Autodesk Fusion 360 part; units mm, degrees
(part 28 of 28)
  line L4452 (8.28, 5.03, -1.4859) -> (8.2704, 5.0319, -1.4859)
  line L4453 (8.2704, 5.0319, -1.4859) -> (8.2569, 5.0454, -1.4859)
  line L4454 (8.2569, 5.0454, -1.4859) -> (8.255, 5.055, -1.4859)
  line L4455 (8.255, 5.055, -1.4859) -> (8.255, 36.805, -1.4859)
  line L4456 (8.255, 36.805, -1.4859) -> (8.2569, 36.8146, -1.4859)
  line L4457 (8.2569, 36.8146, -1.4859) -> (8.2704, 36.8281, -1.4859)
  line L4458 (8.2704, 36.8281, -1.4859) -> (8.28, 36.83, -1.4859)
  line L4459 (8.28, 36.83, -1.4859) -> (66.065, 36.83, -1.4859)
  line L4460 (8.305, 36.78, -1.4859) -> (8.305, 5.08, -1.4859)
  line L4461 (8.305, 5.08, -1.4859) -> (66.04, 5.08, -1.4859)
  line L4462 (66.04, 5.08, -1.4859) -> (66.04, 36.78, -1.4859)
  line L4463 (66.04, 36.78, -1.4859) -> (62.89, 36.78, -1.4859)
  line L4464 (62.89, 36.78, -1.4859) -> (8.305, 36.78, -1.4859)
  line L4465 (127.025, 36.83, -1.4859) -> (127.0346, 36.8281, -1.4859)
  line L4466 (127.0346, 36.8281, -1.4859) -> (127.0481, 36.8146, -1.4859)
  line L4467 (127.0481, 36.8146, -1.4859) -> (127.05, 36.805, -1.4859)
  line L4468 (127.05, 36.805, -1.4859) -> (127.05, 5.055, -1.4859)
  line L4469 (127.05, 5.055, -1.4859) -> (127.0481, 5.0454, -1.4859)
  line L4470 (127.0481, 5.0454, -1.4859) -> (127.0346, 5.0319, -1.4859)
  line L4471 (127.0346, 5.0319, -1.4859) -> (127.025, 5.03, -1.4859)
  line L4472 (127.025, 5.03, -1.4859) -> (69.24, 5.03, -1.4859)
  line L4473 (69.24, 5.03, -1.4859) -> (69.2304, 5.0319, -1.4859)
  line L4474 (69.2304, 5.0319, -1.4859) -> (69.2169, 5.0454, -1.4859)
  line L4475 (69.2169, 5.0454, -1.4859) -> (69.215, 5.055, -1.4859)
  line L4476 (69.215, 5.055, -1.4859) -> (69.215, 36.805, -1.4859)
  line L4477 (69.215, 36.805, -1.4859) -> (69.2169, 36.8146, -1.4859)
  line L4478 (69.2169, 36.8146, -1.4859) -> (69.2304, 36.8281, -1.4859)
  line L4479 (69.2304, 36.8281, -1.4859) -> (69.24, 36.83, -1.4859)
  line L4480 (69.24, 36.83, -1.4859) -> (127.025, 36.83, -1.4859)
  line L4481 (69.265, 36.78, -1.4859) -> (69.265, 5.08, -1.4859)
  line L4482 (69.265, 5.08, -1.4859) -> (127, 5.08, -1.4859)
  line L4483 (127, 5.08, -1.4859) -> (127, 36.78, -1.4859)
  line L4484 (127, 36.78, -1.4859) -> (123.85, 36.78, -1.4859)
  line L4485 (123.85, 36.78, -1.4859) -> (69.265, 36.78, -1.4859)
  line L4486 (40.03, 97.79, -1.4859) -> (43.205, 97.79, -1.4859)
  line L4487 (43.205, 97.79, -1.4859) -> (74.955, 97.79, -1.4859)
  line L4488 (74.955, 97.79, -1.4859) -> (74.9646, 97.7881, -1.4859)
  line L4489 (74.9646, 97.7881, -1.4859) -> (74.9781, 97.7746, -1.4859)
  line L4490 (74.9781, 97.7746, -1.4859) -> (74.98, 97.765, -1.4859)
  line L4491 (74.98, 97.765, -1.4859) -> (74.98, 39.98, -1.4859)
  line L4492 (74.98, 39.98, -1.4859) -> (74.9781, 39.9704, -1.4859)
  line L4493 (74.9781, 39.9704, -1.4859) -> (74.9646, 39.9569, -1.4859)
  line L4494 (74.9646, 39.9569, -1.4859) -> (74.955, 39.955, -1.4859)
  line L4495 (74.955, 39.955, -1.4859) -> (43.205, 39.955, -1.4859)
  line L4496 (43.205, 39.955, -1.4859) -> (43.1954, 39.9569, -1.4859)
  line L4497 (43.1954, 39.9569, -1.4859) -> (43.1819, 39.9704, -1.4859)
  line L4498 (43.1819, 39.9704, -1.4859) -> (43.18, 39.98, -1.4859)
  line L4499 (43.18, 39.98, -1.4859) -> (43.18, 97.74, -1.4859)
  line L4500 (43.18, 97.74, -1.4859) -> (40.055, 97.74, -1.4859)
  line L4501 (40.055, 97.74, -1.4859) -> (40.055, 39.98, -1.4859)
  line L4502 (40.055, 39.98, -1.4859) -> (40.0531, 39.9704, -1.4859)
  line L4503 (40.0531, 39.9704, -1.4859) -> (40.0396, 39.9569, -1.4859)
  line L4504 (40.0396, 39.9569, -1.4859) -> (40.03, 39.955, -1.4859)
  line L4505 (40.03, 39.955, -1.4859) -> (8.28, 39.955, -1.4859)
  line L4506 (8.28, 39.955, -1.4859) -> (8.2704, 39.9569, -1.4859)
  line L4507 (8.2704, 39.9569, -1.4859) -> (8.2569, 39.9704, -1.4859)
  line L4508 (8.2569, 39.9704, -1.4859) -> (8.255, 39.98, -1.4859)
  line L4509 (8.255, 39.98, -1.4859) -> (8.255, 97.765, -1.4859)
  line L4510 (8.255, 97.765, -1.4859) -> (8.2569, 97.7746, -1.4859)
  line L4511 (8.2569, 97.7746, -1.4859) -> (8.2704, 97.7881, -1.4859)
  line L4512 (8.2704, 97.7881, -1.4859) -> (8.28, 97.79, -1.4859)
  line L4513 (8.28, 97.79, -1.4859) -> (40.03, 97.79, -1.4859)
  line L4514 (43.23, 97.74, -1.4859) -> (43.23, 40.005, -1.4859)
  line L4515 (43.23, 40.005, -1.4859) -> (74.93, 40.005, -1.4859)
  line L4516 (74.93, 40.005, -1.4859) -> (74.93, 97.74, -1.4859)
  line L4517 (74.93, 97.74, -1.4859) -> (43.23, 97.74, -1.4859)
  line L4518 (8.305, 97.74, -1.4859) -> (8.305, 40.005, -1.4859)
  line L4519 (8.305, 40.005, -1.4859) -> (40.005, 40.005, -1.4859)
  line L4520 (40.005, 40.005, -1.4859) -> (40.005, 97.74, -1.4859)
  line L4521 (40.005, 97.74, -1.4859) -> (8.305, 97.74, -1.4859)
  line L4522 (109.8896, 97.7881, -1.4859) -> (109.9031, 97.7746, -1.4859)
  line L4523 (109.9031, 97.7746, -1.4859) -> (109.905, 97.765, -1.4859)
  line L4524 (109.905, 97.765, -1.4859) -> (109.905, 39.98, -1.4859)
  line L4525 (109.905, 39.98, -1.4859) -> (109.9031, 39.9704, -1.4859)
  line L4526 (109.9031, 39.9704, -1.4859) -> (109.8896, 39.9569, -1.4859)
  line L4527 (109.8896, 39.9569, -1.4859) -> (109.88, 39.955, -1.4859)
  line L4528 (109.88, 39.955, -1.4859) -> (78.13, 39.955, -1.4859)
  line L4529 (78.13, 39.955, -1.4859) -> (78.1204, 39.9569, -1.4859)
  line L4530 (78.1204, 39.9569, -1.4859) -> (78.1069, 39.9704, -1.4859)
  line L4531 (78.1069, 39.9704, -1.4859) -> (78.105, 39.98, -1.4859)
  line L4532 (78.105, 39.98, -1.4859) -> (78.105, 97.765, -1.4859)
  line L4533 (78.105, 97.765, -1.4859) -> (78.1069, 97.7746, -1.4859)
  line L4534 (78.1069, 97.7746, -1.4859) -> (78.1204, 97.7881, -1.4859)
  line L4535 (78.1204, 97.7881, -1.4859) -> (78.13, 97.79, -1.4859)
  line L4536 (78.13, 97.79, -1.4859) -> (109.88, 97.79, -1.4859)
  line L4537 (109.88, 97.79, -1.4859) -> (109.8896, 97.7881, -1.4859)
  line L4538 (78.155, 97.74, -1.4859) -> (78.155, 40.005, -1.4859)
  line L4539 (78.155, 40.005, -1.4859) -> (109.855, 40.005, -1.4859)
  line L4540 (109.855, 40.005, -1.4859) -> (109.855, 97.74, -1.4859)
  line L4541 (109.855, 97.74, -1.4859) -> (78.155, 97.74, -1.4859)
  line L4542 (144.8146, 97.7881, -1.4859) -> (144.8281, 97.7746, -1.4859)
  line L4543 (144.8281, 97.7746, -1.4859) -> (144.83, 97.765, -1.4859)
  line L4544 (144.83, 97.765, -1.4859) -> (144.83, 39.98, -1.4859)
  line L4545 (144.83, 39.98, -1.4859) -> (144.8281, 39.9704, -1.4859)
  line L4546 (144.8281, 39.9704, -1.4859) -> (144.8146, 39.9569, -1.4859)
  line L4547 (144.8146, 39.9569, -1.4859) -> (144.805, 39.955, -1.4859)
  line L4548 (144.805, 39.955, -1.4859) -> (113.055, 39.955, -1.4859)
  line L4549 (113.055, 39.955, -1.4859) -> (113.0454, 39.9569, -1.4859)
  line L4550 (113.0454, 39.9569, -1.4859) -> (113.0319, 39.9704, -1.4859)
  line L4551 (113.0319, 39.9704, -1.4859) -> (113.03, 39.98, -1.4859)
  line L4552 (113.03, 39.98, -1.4859) -> (113.03, 97.765, -1.4859)
  line L4553 (113.03, 97.765, -1.4859) -> (113.0319, 97.7746, -1.4859)
  line L4554 (113.0319, 97.7746, -1.4859) -> (113.0454, 97.7881, -1.4859)
  line L4555 (113.0454, 97.7881, -1.4859) -> (113.055, 97.79, -1.4859)
  line L4556 (113.055, 97.79, -1.4859) -> (144.805, 97.79, -1.4859)
  line L4557 (144.805, 97.79, -1.4859) -> (144.8146, 97.7881, -1.4859)
  line L4558 (113.08, 97.74, -1.4859) -> (113.08, 40.005, -1.4859)
  line L4559 (113.08, 40.005, -1.4859) -> (144.78, 40.005, -1.4859)
  line L4560 (144.78, 40.005, -1.4859) -> (144.78, 97.74, -1.4859)
  line L4561 (144.78, 97.74, -1.4859) -> (113.08, 97.74, -1.4859)
